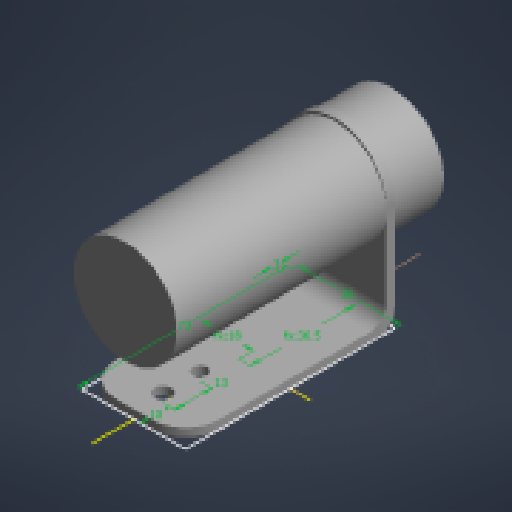
# Autodesk Inventor part: Thermal_Camera
Saved by Autodesk Inventor 2027 (Build 310192000, 192)
## iProperties
Created: 2026-11-09
Part Number: Thermal_Camera
Material: Genérico
Document SubType Name: Modeling
Designer: Jacob Parker
Density: 1 g/cm^3
Appearance: Valor por defecto
Author: Jacob Parker
Autodesk Inventor part; units mm, degrees
ref_plane "YZ Plane" through (0, 0, 0) normal (1, 0, 0) x (0, 1, 0)
ref_plane "XZ Plane" through (0, 0, 0) normal (0, 1, 0) x (-1, 0, 0)
ref_plane "XY Plane" through (0, 0, 0) normal (0, 0, 1) x (1, 0, 0)
sketch "baseSK" plane through (0, 0, 0) normal (0, 1, 0) x (-1, 0, 0)
  line L0 (18, 36.5) -> (-18, 36.5)
  line L1 (-18, 36.5) -> (-18, -36.5)
  line L2 (-18, -36.5) -> (18, -36.5)
  line L3 (18, -36.5) -> (18, 36.5)
  line L4 (25.2, 0) -> (-25.2, 0) projected
  line L5 (0, -51.1) -> (0, 51.1) projected
  line L6 (18, -36.5) -> (-18, -36.5)
  line L7 (-18, -36.5) -> (-18, -33.5)
  line L8 (-18, -33.5) -> (18, -33.5)
  line L9 (18, -33.5) -> (18, -36.5)
  point P0 (0, 0)
  point P1 (0, 26.5)
  point P2 (0, 13.5)
  dimension "d0" = 73
  dimension "d1" = 36
  dimension "d2" = 18
  dimension "d3" = 36.5
  dimension "d7" = 3
  dimension "d17" = 10
  dimension "d18" = 13
  constraints: 16 end point, 4 parallel, 3 point on line, 2 horizontal, 2 perpendicular
  measures "d0" distance of L2.end L0.start
  measures "d1" distance of L1.end L2.end
  measures "d2" distance from line of point (0, 0) L3
  measures "d3" distance from line of point (0, 0) L2
  measures "d7" distance between parallel lines of L2 L8
  measures "d17" distance from line of L0 point (0, 26.5)
  measures "d18" distance of point (0, 26.5) point (0, 13.5)
extrude "baseEX" add sketch "baseSK" along normal blind 3 contours L3 L4 L5 L0 | L5 L4 L1 L0 | L3 L8 L5 L4 | L5 L8 L1 L4
extrude "jointEX" add sketch "baseSK" along normal blind 56 contours L3 L2 L5 L8 | L5 L2 L1 L8
fillet "bigF" radius 18 2 edges at (18, 56, -35) (-18, 56, -35)
sketch "camSK" plane through (-18, 3, -33.5) normal (0, 0, 1) x (1, 0, 0)
  circle A0 centre (18, 34) radius 18
  point P0 (18, -3)
  point P1 (0, 35)
  dimension "d11" = 36
  constraints: 1 centre point
  measures "d11" diameter of A0
extrude "camEX" add sketch "camSK" along normal blind 73 and the other way blind 20
fillet "smallF" radius 12 2 edges at (18, 1.5, 36.5) (-18, 1.5, 36.5)
hole "bigH" at (0, 0, 26.5) direction (0, 1, 0) diameter 6 depth 3
hole "smallH" at (0, 0, 13.5) direction (0, 1, 0) diameter 5 depth 3
fillet "Fillet3" radius 6 2 edges at (0, 3, -33.5) (0, 0, -36.5)
equation "\"d2\" = 0.5 * d1"
equation "\"d3\" = 0.5 * d0"
equation "\"d24\" = d7"
equation "\"d31\" = d7"
body "Solid1"
